MHCCase (Autodesk Fusion 360 design; units mm, degrees)
Autodesk Fusion 360 part; units mm, degrees
sketch "Sketch1" plane through (0, 0, 0) normal (0, 1, 0) x (1, 0, 0)
  line L0 (53, 80.5) -> (-53, 80.5)
  line L1 (-53, 80.5) -> (-53, -74.5)
  line L2 (-53, -74.5) -> (53, -74.5)
  line L3 (53, -74.5) -> (53, 80.5)
  line L4 (-50, -71.5) -> (50, -71.5)
  line L5 (50, -71.5) -> (50, -4.5)
  line L6 (50, -4.5) -> (-50, -4.5)
  line L7 (-50, -4.5) -> (-50, -71.5)
  line L8 (-50, -1.5) -> (0, -1.5)
  line L9 (0, -1.5) -> (0, 49.5)
  line L10 (0, 49.5) -> (-50, 49.5)
  line L11 (-50, 49.5) -> (-50, -1.5)
  line L12 (0, -1.5) -> (0, 66)
  line L13 (0, -74.5) -> (0, -71.5)
  line L14 (-50, 49.5) -> (-50, 50.5)
  line L15 (-50, 50.5) -> (-43.5, 50.5)
  line L16 (-43.5, 50.5) -> (-43.5, 78.5)
  line L17 (-43.5, 78.5) -> (-50, 78.5)
  line L18 (-50, 78.5) -> (-50, 50.5)
  line L19 (-43.5, 50.5) -> (-42.5, 50.5)
  line L20 (-42.5, 50.5) -> (-36, 50.5)
  line L21 (-36, 50.5) -> (-36, 78.5)
  line L22 (-36, 78.5) -> (-42.5, 78.5)
  line L23 (-42.5, 78.5) -> (-42.5, 50.5)
  line L24 (-36, 50.5) -> (-35, 50.5)
  line L25 (-35, 50.5) -> (-1, 50.5)
  line L26 (-1, 50.5) -> (-1, 62.5)
  line L27 (-1, 62.5) -> (-35, 62.5)
  line L28 (-35, 62.5) -> (-35, 50.5)
  line L29 (-1, 62.5) -> (0, 62.5)
  line L30 (-35, 62.5) -> (-35, 67)
  line L31 (-35, 67) -> (0.5, 67)
  line L32 (0.5, 67) -> (0.5, 74)
  line L33 (0.5, 74) -> (-35, 74)
  line L34 (-35, 74) -> (-35, 67)
  line L35 (0, -1.5) -> (50.5, -1.5)
  line L36 (50.5, -1.5) -> (50.5, 66)
  line L37 (50.5, 66) -> (0, 66)
  dimension "d16" = 155
  dimension "d17" = 3
  dimension "d18" = 1
  dimension "d19" = 28
  dimension "d20" = 6.5
  dimension "d21" = 1
  dimension "d22" = 6.5
  dimension "d23" = 28
  dimension "d24" = 1
  dimension "d25" = 34
  dimension "d26" = 12
  dimension "d27" = 4.5
  dimension "d28" = 35.5
  dimension "d29" = 7
  dimension "d64" = 50.5
  constraint parallel L1 L3
  constraint horizontal L0
  constraint horizontal L4
  constraint vertical L5
  constraint vertical L7
  constraint horizontal L8
  constraint vertical L9
  constraint horizontal L10
  constraint vertical L11
  constraint vertical L12
  constraint midpoint L2 L13.start
  constraint perpendicular L4 L13
  constraint perpendicular L10 L14
  constraint horizontal L15
  constraint vertical L16
  constraint horizontal L17
  constraint vertical L18
  constraint perpendicular L16 L19
  constraint horizontal L20
  constraint vertical L21
  constraint horizontal L22
  constraint vertical L23
  constraint perpendicular L12 L24
  constraint horizontal L25
  constraint vertical L26
  constraint horizontal L27
  constraint vertical L28
  constraint coincident L12 L29.end
  constraint perpendicular L12 L29
  constraint perpendicular L27 L30
  constraint horizontal L31
  constraint vertical L32
  constraint horizontal L33
  constraint vertical L34
  constraint perpendicular L12 L35
  constraint perpendicular L35 L36
  measures "d16" distance of L0.start L2.end
  measures "d17" distance of L13.start L13.end
  measures "d18" distance of L10.end L14.end
  measures "d19" distance of L14.end L17.end
  measures "d20" distance of L14.end L15.end
  measures "d21" distance of L15.end L19.end
  measures "d22" distance of L19.end L20.end
  measures "d23" distance of L19.end L22.end
  measures "d24" distance of L20.end L24.end
  measures "d25" distance of L24.end L25.end
  measures "d26" distance of L24.end L27.end
  measures "d27" distance of L27.end L30.end
  measures "d28" distance of L30.end L31.end
  measures "d29" distance of L30.end L33.end
  measures "d64" distance of L8.end L35.end
extrude "Extrude1" add sketch "Sketch1" along normal blind 32 contours L0 L1 L2 L3 | L4 L5 L6 L7 | L8 L9 L10 L11 L12 | L9 L12 L35 L36 L37 | L10 L12 L14 L15 L19 L20 L24 L25 L26 L29 | L15 L16 L17 L18 | L25 L26 L27 L28 | L20 L21 L22 L23 | L31 L32 L33 L34
extrude "Extrude2" cut sketch "Sketch1" along normal blind 23 contours L4 L5 L6 L7
extrude "Extrude3" cut sketch "Sketch1" along normal blind 2 contours L9 L12 L35 L36 L37
extrude "Extrude4" cut sketch "Sketch1" along normal blind 24 contours L8 L9 L10 L11 L12
extrude "Extrude5" cut sketch "Sketch1" along normal blind 24 contours L15 L16 L17 L18 | L20 L21 L22 L23
extrude "Extrude6" cut sketch "Sketch1" along normal blind 9 contours L25 L26 L27 L28
extrude "Extrude7" cut sketch "Sketch1" along normal blind 1 contours L31 L32 L33 L34
sketch "Sketch2" plane through (0, 9, 0) normal (0, -1, 0) x (1, 0, 0)
  line L0 (-35, -50.5) -> (-35, -62.5)
  line L1 (-35, -62.5) -> (-1, -62.5)
  line L2 (-1, -62.5) -> (-1, -50.5)
  line L3 (-1, -50.5) -> (-35, -50.5)
  line L4 (-35, -62.5) -> (-35, -59)
  line L5 (-35, -59) -> (-1, -59)
  dimension "d44" = 3.5
  dimension "d45" = 34
  constraint coincident L0.end L1.start
  constraint perpendicular L1 L4
  constraint perpendicular L2 L5
  measures "d44" distance of L0.end L4.end
  measures "d45" distance of L4.end L5.end
extrude "Extrude8" cut sketch "Sketch2" against normal blind 23 contours L0 L1 L2 L4 L5
sketch "Sketch3" plane through (0, 32, 0) normal (0, 1, 0) x (-1, 0, 0)
  line L0 (1, -62.5) -> (1, -59)
  line L1 (1, -59) -> (35, -59)
  line L2 (35, -59) -> (35, -62.5)
  line L3 (35, -62.5) -> (1, -62.5)
  line L4 (-53, 74.5) -> (-53, -80.5)
  line L5 (-53, -80.5) -> (53, -80.5)
  line L6 (53, -80.5) -> (53, 74.5)
  line L7 (53, 74.5) -> (-53, 74.5)
extrude "Extrude9" add sketch "Sketch3" against normal blind 1 contours L0 L1 L2 L3 | L4 L5 L6 L7
sketch "Sketch4" plane through (0, 1, 0) normal (0, -1, 0) x (1, 0, 0)
  line L0 (-35, -67) -> (-35, -74)
  line L1 (-35, -74) -> (0.5, -74)
  line L2 (0.5, -74) -> (0.5, -67)
  line L3 (0.5, -67) -> (-35, -67)
  line L4 (-35, -67) -> (-17.25, -67)
  line L5 (-17.25, -67) -> (-17.25, -70.5)
  line L6 (0.5, -71.5) -> (-35, -71.5)
  line L7 (-35, -71.5) -> (-35, -69.5)
  line L8 (-35, -69.5) -> (0.5, -69.5)
  line L9 (0.5, -69.5) -> (0.5, -71.5)
  line L10 (0.5, -71.5) -> (-35, -69.5) construction
  line L11 (-35, -71.5) -> (0.5, -69.5) construction
  point P0 (-17.25, -70.5)
  dimension "d50" = 3.5
  dimension "d51" = 2
  constraint coincident L0.start L3.end
  constraint midpoint L3 L4.end
  constraint perpendicular L1 L5
  constraint perpendicular L6 L7
  constraint parallel L6 L8
  constraint parallel L7 L9
  constraint horizontal L6
  constraint coincident L10 P0
  constraint coincident L11 P0
  constraint coincident P0 L5.end
  measures "d50" distance of L4.end P0
  measures "d51" distance of L6.end L7.end
extrude "Extrude10" cut sketch "Sketch4" against normal blind 21 contours L0 L2 L6 L7 L8 L9
sketch "Sketch5" plane through (0, 2, 0) normal (0, -1, 0) x (1, 0, 0)
  line L0 (50.5, 1.5) -> (0, 1.5)
  line L1 (0, 1.5) -> (0, -49.5)
  line L2 (0, -49.5) -> (0, -66)
  line L3 (0, 1.5) -> (0, -1.5)
  circle A0 centre (3, -1.5) radius 2.5
  line L4 (3, -1.5) -> (3, -45.75)
  line L5 (3, -45.75) -> (47.5, -45.75)
  line L6 (3, -1.5) -> (47.5, -1.5)
  circle A1 centre (3, -45.75) radius 2.5
  circle A2 centre (47.5, -45.75) radius 2.5
  circle A3 centre (47.5, -1.5) radius 2.5
  line L7 (50.5, -66) -> (50.5, 1.5)
  line L8 (0, -66) -> (50.5, -66)
  dimension "d54" = 3
  dimension "d56" = 5
  dimension "d57" = 44.25
  dimension "d58" = 44.5
  dimension "d59" = 44.5
  dimension "d60" = 5
  dimension "d61" = 5
  dimension "d62" = 5
  constraint coincident L0.end L1.start
  constraint perpendicular L0 L3
  constraint coincident A0.centre L4.start
  constraint vertical L4
  constraint perpendicular L4 L5
  constraint perpendicular L4 L6
  constraint coincident L4.end L5.start
  constraint coincident L5.end A2.centre
  constraint coincident L6.end A3.centre
  measures "d54" distance of L0.end L3.end
  measures "d56" diameter of A0
  measures "d57" distance of A0.centre L4.end
  measures "d58" distance of L4.end L5.end
  measures "d59" distance of A0.centre L6.end
  measures "d60" diameter of A1
  measures "d61" diameter of A2
  measures "d62" diameter of A3
extrude "Extrude11" cut sketch "Sketch5" against normal blind 9.5 contours A0 L4 L6 | A0 L4 L6 | L4 L5 A1 | L4 L5 A1 | A2 | A3
sketch "Sketch6" plane through (0, 24, 0) normal (0, -1, 0) x (1, 0, 0)
  line L0 (0, -49.5) -> (0, 1.5)
  line L1 (0, 1.5) -> (-50, 1.5)
  line L2 (-50, 1.5) -> (-50, -49.5)
  line L3 (-50, -49.5) -> (0, -49.5)
  line L4 (-50, -49.5) -> (-25, -49.5)
  line L5 (-25, -49.5) -> (-25, -46)
  line L6 (-25, -46) -> (-13.75, -46)
  line L7 (-13.75, -46) -> (-36.25, -46)
  line L8 (-36.25, -46) -> (-36.25, -42.5)
  line L9 (-36.25, -42.5) -> (-13.75, -42.5)
  line L10 (-13.75, -42.5) -> (-13.75, -46)
  line L11 (-50, -49.5) -> (-50, -46)
  line L12 (-50, -46) -> (-46.5, -46)
  line L13 (0, 1.5) -> (-3.5, 1.5)
  line L14 (-3.5, 1.5) -> (-3.5, -2)
  line L15 (-3.5, -2) -> (-46.5, -2)
  line L16 (-46.5, -2) -> (-46.5, -46)
  line L17 (-46.5, -46) -> (-3.5, -46)
  line L18 (-3.5, -46) -> (-3.5, -2)
  line L19 (-25, -42.5) -> (-25, -4.95)
  line L20 (-25, -23.725) -> (-43.725, -23.725)
  line L21 (-25, -23.725) -> (-6.275, -23.725)
  line L22 (-43.725, -23.725) -> (-43.725, -34.975)
  line L23 (-6.275, -23.725) -> (-6.275, -34.975)
  line L24 (-25, -4.95) -> (-36.25, -4.95)
  line L25 (-36.25, -4.95) -> (-13.75, -4.95)
  line L26 (-13.75, -4.95) -> (-13.75, -1.45)
  line L27 (-13.75, -1.45) -> (-36.25, -1.45)
  line L28 (-36.25, -1.45) -> (-36.25, -4.95)
  line L29 (-6.275, -34.975) -> (-2.775, -34.975)
  line L30 (-2.775, -34.975) -> (-2.775, -12.475)
  line L31 (-2.775, -12.475) -> (-6.275, -12.475)
  line L32 (-6.275, -12.475) -> (-6.275, -34.975)
  line L33 (-43.725, -34.975) -> (-47.225, -34.975)
  line L34 (-47.225, -34.975) -> (-47.225, -12.475)
  line L35 (-47.225, -12.475) -> (-43.725, -12.475)
  line L36 (-43.725, -12.475) -> (-43.725, -34.975)
  dimension "d72" = 3.5
  dimension "d73" = 3.5
  dimension "d74" = 3.5
  dimension "d75" = 3.5
  dimension "d76" = 37.55
  dimension "d77" = 3.5
  dimension "d78" = 22.5
  dimension "d79" = 18.725
  dimension "d80" = 18.725
  dimension "d81" = 11.25
  dimension "d82" = 11.25
  dimension "d83" = 11.25
  dimension "d84" = 22.5
  dimension "d85" = 3.5
  dimension "d86" = 22.5
  dimension "d87" = 3.5
  dimension "d88" = 22.5
  dimension "d89" = 3.5
  constraint coincident L2.end L3.start
  constraint midpoint L3 L4.end
  constraint perpendicular L4 L5
  constraint perpendicular L5 L6
  constraint horizontal L7
  constraint vertical L8
  constraint horizontal L9
  constraint vertical L10
  constraint perpendicular L4 L11
  constraint perpendicular L2 L12
  constraint coincident L0.end L1.start
  constraint perpendicular L0 L13
  constraint perpendicular L13 L14
  constraint horizontal L15
  constraint vertical L16
  constraint horizontal L17
  constraint vertical L18
  constraint midpoint L9 L19.start
  constraint perpendicular L9 L19
  constraint midpoint L19 L20.start
  constraint perpendicular L19 L20
  constraint perpendicular L19 L21
  constraint perpendicular L20 L22
  constraint perpendicular L21 L23
  constraint perpendicular L19 L24
  constraint horizontal L25
  constraint vertical L26
  constraint horizontal L27
  constraint vertical L28
  constraint horizontal L29
  constraint vertical L30
  constraint horizontal L31
  constraint vertical L32
  constraint horizontal L33
  constraint vertical L34
  constraint horizontal L35
  constraint vertical L36
  measures "d72" distance of L2.end L11.end
  measures "d73" distance of L11.end L12.end
  measures "d74" distance of L0.end L13.end
  measures "d75" distance of L13.end L14.end
  measures "d76" distance of L19.start L19.end
  measures "d77" distance of L6.end L9.end
  measures "d78" distance of L8.end L9.end
  measures "d79" distance of L20.start L20.end
  measures "d80" distance of L20.start L21.end
  measures "d81" distance of L20.end L22.end
  measures "d82" distance of L21.end L23.end
  measures "d83" distance of L19.end L24.end
  measures "d84" distance of L24.end L25.end
  measures "d85" distance of L24.end L27.end
  measures "d86" distance of L23.end L31.end
  measures "d87" distance of L23.end L29.end
  measures "d88" distance of L22.end L35.end
  measures "d89" distance of L22.end L33.end
extrude "Extrude12" cut sketch "Sketch6" against normal blind 6 contours L6 L7 L8 L9 L10 L17 | L15 L24 L25 L26 L28 | L15 L26 L27 L28 | L18 L29 L30 L31 | L18 L23 L29 L31 L32 | L16 L33 L34 L35 | L16 L22 L33 L35 L36
sketch "Sketch7" plane through (0, 32, 0) normal (0, 1, 0) x (-1, 0, 0)
  line L0 (-53, 74.5) -> (-53, -80.5)
  line L1 (-53, -80.5) -> (53, -80.5)
  line L2 (53, -80.5) -> (53, 74.5)
  line L3 (53, 74.5) -> (-53, 74.5)
  line L4 (53, -80.5) -> (53, -89.5)
  line L5 (53, -89.5) -> (62, -89.5)
  line L6 (-53, 74.5) -> (-62, 74.5)
  line L7 (-62, 74.5) -> (-62, 83.5)
  line L8 (62, -89.5) -> (-62, -89.5)
  line L9 (-62, -89.5) -> (-62, 83.5)
  line L10 (-62, 83.5) -> (62, 83.5)
  line L11 (62, 83.5) -> (62, -89.5)
  dimension "d94" = 9
  dimension "d95" = 9
  dimension "d96" = 9
  dimension "d97" = 9
  constraint coincident L1.end L2.start
  constraint perpendicular L1 L4
  constraint perpendicular L4 L5
  constraint coincident L0.start L3.end
  constraint perpendicular L0 L6
  constraint perpendicular L6 L7
  constraint horizontal L8
  constraint vertical L9
  constraint horizontal L10
  constraint vertical L11
  measures "d94" distance of L1.end L4.end
  measures "d95" distance of L4.end L5.end
  measures "d96" distance of L0.start L6.end
  measures "d97" distance of L6.end L7.end
extrude "Extrude13" add sketch "Sketch7" against normal blind 28 contours L2 L3 L4 L5 L6 L7 L8 L9 L10 L11 | L0 L1 L4 L6 L8 L9
sketch "Sketch8" plane through (0, 0, 1.5) normal (0, 0, -1) x (-1, 0, 0)
  line L0 (-50.5, 0) -> (50, 0)
  line L1 (50, 0) -> (50, 24)
  line L2 (50, 24) -> (0, 24)
  line L3 (0, 24) -> (0, 2)
  line L4 (0, 2) -> (-50.5, 2)
  line L5 (-50.5, 2) -> (-50.5, 0)
extrude "Extrude14" cut sketch "Sketch8" against normal blind 1
sketch "Sketch9" plane through (-50, 0, 0) normal (1, 0, 0) x (0, 0, -1)
  line L0 (-2.5, 0) -> (49.5, 0)
  line L1 (49.5, 0) -> (49.5, 24)
  line L2 (49.5, 24) -> (-2.5, 24)
  line L3 (-2.5, 24) -> (-2.5, 0)
extrude "Extrude15" cut sketch "Sketch9" against normal blind 1
sketch "Sketch10" plane through (0, 2, 0) normal (0, -1, 0) x (1, 0, 0)
  circle A0 centre (3, -45.75) radius 2.5
  circle A1 centre (47.5, -45.75) radius 2.5
  circle A2 centre (3, -1.5) radius 2.5
  circle A3 centre (47.5, -1.5) radius 2.5
  line L0 (50.5, -66) -> (50.5, 2.5)
  line L1 (50.5, 2.5) -> (0, 2.5)
  line L2 (0, 2.5) -> (0, -49.5)
  line L3 (0, -49.5) -> (0, -66)
  line L4 (0, -66) -> (50.5, -66)
  line L5 (26.9677, 2.5) -> (26.9677, -8.5)
  line L6 (26.9677, -8.5) -> (-2, -8.5)
  line L7 (0, -8.5) -> (50.5, -8.5)
  dimension "d104" = 11
  constraint coincident L1 L5.start
  constraint perpendicular L1 L5
  constraint perpendicular L2 L6
  constraint coincident L6 L7.start
  constraint coincident L2 L7.start
  constraint coincident L0 L7.end
  constraint horizontal L7
  measures "d104" distance of L5.start L5.end
sketch "Sketch11" plane through (50.5, 0, 0) normal (-1, 0, 0) x (0, 0, 1)
  line L0 (-66, 0) -> (2.5, 0)
  line L1 (2.5, 0) -> (2.5, 2)
  line L2 (2.5, 2) -> (-66, 2)
  line L3 (-66, 2) -> (-66, 0)
extrude "Extrude16" cut sketch "Sketch11" against normal blind 0.5
sketch "Sketch12" plane through (0, 24, 0) normal (0, -1, 0) x (1, 0, 0)
  line L0 (-47.225, -34.975) -> (-47.225, -12.475)
  line L1 (-47.225, -12.475) -> (-43.725, -12.475)
  line L2 (-43.725, -12.475) -> (-43.725, -34.975)
  line L3 (-43.725, -34.975) -> (-47.225, -34.975)
  line L4 (-13.75, -42.5) -> (-13.75, -46)
  line L5 (-13.75, -46) -> (-36.25, -46)
  line L6 (-36.25, -46) -> (-36.25, -42.5)
  line L7 (-36.25, -42.5) -> (-13.75, -42.5)
  line L8 (-13.75, -4.95) -> (-36.25, -4.95)
  line L9 (-36.25, -4.95) -> (-36.25, -1.45)
  line L10 (-36.25, -1.45) -> (-13.75, -1.45)
  line L11 (-13.75, -1.45) -> (-13.75, -4.95)
  line L12 (-2.775, -34.975) -> (-6.275, -34.975)
  line L13 (-6.275, -34.975) -> (-6.275, -12.475)
  line L14 (-6.275, -12.475) -> (-2.775, -12.475)
  line L15 (-2.775, -12.475) -> (-2.775, -34.975)
  line L16 (0, -49.5) -> (0, 2.5)
  line L17 (0, 2.5) -> (-51, 2.5)
  line L18 (-51, 2.5) -> (-51, -49.5)
  line L19 (-51, -49.5) -> (0, -49.5)
extrude "Extrude17" add sketch "Sketch12" along normal blind 5
sketch "Sketch13" plane through (0, 2, 0) normal (0, -1, 0) x (1, 0, 0)
  circle A0 centre (3, -45.75) radius 2.5
  circle A1 centre (47.5, -45.75) radius 2.5
  circle A2 centre (3, -1.5) radius 2.5
  circle A3 centre (47.5, -1.5) radius 2.5
  line L0 (51, 2.5) -> (0, 2.5)
  line L1 (0, 2.5) -> (0, -49.5)
  line L2 (0, -49.5) -> (0, -66)
  line L3 (0, -66) -> (50.5, -66)
  line L4 (50.5, -66) -> (51, -66)
  line L5 (51, -66) -> (51, 2.5)
  line L6 (0, 2.5) -> (0, -8.5)
  line L7 (0, -8.5) -> (51, -8.5)
  dimension "d109" = 11
  constraint coincident L0.end L1.start
  constraint perpendicular L0 L6
  constraint coincident L5 L7.end
  constraint horizontal L7
  measures "d109" distance of L0.end L6.end
extrude "Extrude18" cut sketch "Sketch13" against normal blind 3 contours L0 L1 L5 L6 L7
sketch "Sketch14" plane through (0, 0, -89.5) normal (0, 0, -1) x (-1, 0, 0)
  line L0 (62, 32) -> (-62, 32)
  line L1 (-62, 32) -> (-62, 4)
  line L2 (-62, 4) -> (62, 4)
  line L3 (62, 4) -> (62, 32)
  line L4 (-31.5778, 4) -> (-31.5778, 6)
  line L5 (-31.4958, 32) -> (-31.4958, 30)
  line L6 (-7.5, 6) -> (-31.5778, 6)
  line L7 (-44, 6) -> (-31.5778, 6)
  line L8 (-7.5, 6) -> (-43, 6)
  line L9 (-43, 6) -> (-43, 27)
  line L10 (-43, 27) -> (-7.5, 27)
  line L11 (-7.5, 27) -> (-7.5, 6)
  dimension "d112" = 2
  constraint coincident L2 L4.start
  constraint perpendicular L2 L4
  constraint coincident L0 L5.start
  constraint perpendicular L0 L5
  constraint perpendicular L4 L6
  constraint perpendicular L4 L7
  constraint horizontal L8
  constraint vertical L9
  constraint horizontal L10
  constraint vertical L11
  measures "d112" distance of L5.start L5.end
extrude "Extrude19" cut sketch "Sketch14" against normal blind 90 contours L6 L7 L8 L9 L10 L11
sketch "Sketch15" plane through (0, 27, 0) normal (0, -1, 0) x (1, 0, 0)
  line L0 (7.5, -89.5) -> (43, -89.5)
  line L1 (43, -89.5) -> (43, 0.5)
  line L2 (43, 0.5) -> (7.5, 0.5)
  line L3 (7.5, 0.5) -> (7.5, -89.5)
  line L4 (7.5, -89.5) -> (25.25, -89.5)
  line L5 (25.25, -89.5) -> (25.25, -79.5)
  circle A0 centre (25.25, -79.5) radius 2.5
  dimension "d115" = 10
  dimension "d116" = 5
  constraint coincident L0.start L3.end
  constraint midpoint L0 L4.end
  constraint perpendicular L4 L5
  constraint coincident L5.end A0.centre
  measures "d115" distance of L4.end L5.end
  measures "d116" diameter of A0
extrude "Extrude20" cut sketch "Sketch15" against normal blind 3 contours A0
chamfer "Chamfer2" distance 0.5 angle 45 1 edges at (22.9192, 27, -78.596) tangent chain off
sketch "Sketch16" plane through (0, 4, 0) normal (0, -1, 0) x (1, 0, 0)
  line L0 (-53, 74.5) -> (53, 74.5)
  line L1 (53, 74.5) -> (53, -80.5)
  line L2 (53, -80.5) -> (-53, -80.5)
  line L3 (-53, -80.5) -> (-53, 74.5)
  line L4 (62, 83.5) -> (-62, 83.5)
  line L5 (-62, 83.5) -> (-62, -89.5)
  line L6 (-62, -89.5) -> (62, -89.5)
  line L7 (62, -89.5) -> (62, 83.5)
  circle A0 centre (56.5, -84) radius 2.575
  circle A1 centre (56.5, 78) radius 2.575
  circle A2 centre (-56.5, 78) radius 2.575
  circle A3 centre (-56.5, -84) radius 2.575
  dimension "d122" = 5.15
  dimension "d123" = 5.15
  dimension "d124" = 5.15
  dimension "d125" = 5.15
  measures "d122" diameter of A0
  measures "d123" diameter of A1
  measures "d124" diameter of A2
  measures "d125" diameter of A3
extrude "Extrude21" cut sketch "Sketch16" against normal blind 3 contours A0 | A1 | A2 | A3
chamfer "Chamfer3" distance 0.5 angle 45 4 edges at (-58.9007, 4, -83.0688) (54.0993, 4, -83.0688) (54.0993, 4, 78.9312) (-58.9007, 4, 78.9312) tangent chain off
chamfer "Chamfer4" distance 0.5 angle 45 4 edges at (0, 0, -80.5) (53, 0, -3) (0, 0, 74.5) (-53, 0, -3) tangent chain off
fillet "Fillet2" radius 5 4 edges at (-62, 18, -89.5) (62, 18, -89.5) (-62, 18, 83.5) (62, 18, 83.5)
chamfer "Chamfer5" distance 3 angle 45 1 edges at (25.5, 2, -8.5) tangent chain off
fillet "Fillet3" radius 2 1 edges at (25.5, 2, -11.5)
sketch "Sketch17" plane through (0, 32, 0) normal (0, 1, 0) x (-1, 0, 0)
  arc A0 (-57, 83.5) -> (-62, 78.5) centre (-57, 78.5) ccw
  line L0 (-62, 78.5) -> (-62, -84.5)
  arc A1 (-62, -84.5) -> (-57, -89.5) centre (-57, -84.5) ccw
  line L1 (-57, -89.5) -> (57, -89.5)
  arc A2 (57, -89.5) -> (62, -84.5) centre (57, -84.5) ccw
  line L2 (62, -84.5) -> (62, 78.5)
  arc A3 (62, 78.5) -> (57, 83.5) centre (57, 78.5) ccw
  line L3 (57, 83.5) -> (-57, 83.5)
